Untitled (W-8tPPNV) (Autodesk Fusion 360 design; units mm, degrees)
Autodesk Fusion 360 part; units mm, degrees
sketch "Sketch1" plane through (0, 0, 0) normal (0, 1, 0) x (1, 0, 0)
  line L0 (5, -5) -> (-5, -5)
  line L1 (-5, -5) -> (-5, 5)
  line L2 (-5, 5) -> (5, 5)
  line L3 (5, 5) -> (5, -5)
  line L4 (2, -2) -> (-2, -2)
  line L5 (-2, -2) -> (-2, 2)
  line L6 (-2, 2) -> (2, 2)
  line L7 (2, 2) -> (2, -2)
  line L8 (0, 0) -> (-5, 5)
  line L9 (0, 0) -> (5, 5)
  line L10 (0, 0) -> (5, -5)
  line L11 (0, 0) -> (-5, -5)
  line L12 (-2.6745, 2.6745) -> (-3.0281, 2.321)
  line L13 (-2.6745, 2.6745) -> (-2.321, 3.0281)
  line L14 (2.8513, 2.8513) -> (3.2048, 2.4977)
  line L15 (2.8513, 2.8513) -> (2.4977, 3.2048)
  line L16 (3.0634, -3.0634) -> (2.7099, -3.417)
  line L17 (3.0634, -3.0634) -> (3.417, -2.7099)
  line L18 (-3.276, -3.276) -> (-3.6296, -2.9225)
  line L19 (-3.276, -3.276) -> (-2.9225, -3.6296)
  line L20 (-3.6296, -2.9225) -> (-1.3404, -0.6333)
  line L21 (-3.6296, -2.9225) -> (-5.7188, -5.0117)
  line L22 (-2.9225, -3.6296) -> (-0.6633, -1.3704)
  line L23 (-2.9225, -3.6296) -> (-5.0817, -5.7888)
  line L24 (-3.0281, 2.321) -> (-1.0788, 0.3717)
  line L25 (-3.0281, 2.321) -> (-5.7071, 5)
  line L26 (-2.321, 3.0281) -> (-5.3299, 6.037)
  line L27 (-2.321, 3.0281) -> (-0.2417, 0.9488)
  line L28 (2.4977, 3.2048) -> (0.4989, 1.206)
  line L29 (3.2048, 2.4977) -> (1.356, 0.6489)
  line L30 (2.4977, 3.2048) -> (5.6371, 6.3442)
  line L31 (3.2048, 2.4977) -> (6.2643, 5.5571)
  line L32 (3.417, -2.7099) -> (6.202, -5.4949)
  line L33 (2.7099, -3.417) -> (5.6299, -6.337)
  line L34 (2.7099, -3.417) -> (0.5835, -1.2907)
  line L35 (3.417, -2.7099) -> (1.3878, -0.6807)
  line L36 (-5, -5) -> (-4.2929, -4.2929)
  line L37 (-4.2929, -4.2929) -> (-3.0481, -5.5377)
  line L38 (-4.2929, -4.2929) -> (-5.4934, -3.0924)
  line L39 (-4.2929, -4.2929) -> (-3.8686, -3.8686)
  line L40 (-3.8686, -3.8686) -> (-5.7736, -1.9636)
  line L41 (-3.8686, -3.8686) -> (-1.4498, -6.2875)
  line L42 (5, -5) -> (4.2929, -4.2929)
  line L43 (-4.2929, -4.2929) -> (-4.0808, -4.505)
  line L44 (-4.2929, -4.2929) -> (-4.505, -4.0808)
  line L45 (-4.505, -4.0808) -> (-5.9877, -5.5634)
  line L46 (-4.0808, -4.505) -> (-5.3646, -5.7888)
  line L47 (4.2929, -4.2929) -> (2.8736, -5.7122)
  line L48 (4.2929, -4.2929) -> (5.8776, -2.7082)
  line L49 (4.2929, -4.2929) -> (4.505, -4.0808)
  line L50 (4.2929, -4.2929) -> (4.0808, -4.505)
  line L51 (4.0808, -4.505) -> (5.6075, -6.0318)
  line L52 (4.505, -4.0808) -> (6.2423, -5.8181)
  line L53 (4.2929, -4.2929) -> (3.8686, -3.8686)
  line L54 (3.8686, -3.8686) -> (5.8582, -1.879)
  line L55 (3.8686, -3.8686) -> (1.9311, -5.8061)
  line L56 (5, 5) -> (4.2929, 4.2929)
  line L57 (4.2929, 4.2929) -> (2.5, 6.0858)
  line L58 (4.2929, 4.2929) -> (6.5174, 2.0684)
  line L59 (4.2929, 4.2929) -> (3.8686, 3.8686)
  line L60 (3.8686, 3.8686) -> (1.9516, 5.7856)
  line L61 (3.8686, 3.8686) -> (5.6131, 2.1242)
  line L62 (4.2929, 4.2929) -> (4.0808, 4.505)
  line L63 (4.2929, 4.2929) -> (4.505, 4.0808)
  line L64 (4.0808, 4.505) -> (5.7085, 6.1328)
  line L65 (4.505, 4.0808) -> (6.2385, 5.8143)
  line L66 (-5, 5) -> (-4.2929, 4.2929)
  line L67 (-4.2929, 4.2929) -> (-5.6626, 2.9232)
  line L68 (-4.2929, 4.2929) -> (-2.644, 5.9418)
  line L69 (-4.2929, 4.2929) -> (-3.8686, 3.8686)
  line L70 (-3.8686, 3.8686) -> (-5.6859, 2.0514)
  line L71 (-3.8686, 3.8686) -> (-1.7234, 6.0139)
  line L72 (-4.2929, 4.2929) -> (-4.505, 4.0808)
  line L73 (-4.2929, 4.2929) -> (-4.0808, 4.505)
  line L74 (-4.0808, 4.505) -> (-7.0017, 7.426)
  line L75 (-4.505, 4.0808) -> (-6.1404, 5.7162)
  dimension "d5" = 0.5
  dimension "d6" = 0.5
  dimension "d7" = 0.5
  dimension "d8" = 0.5
  dimension "d9" = 0.5
  dimension "d10" = 0.5
  dimension "d11" = 0.5
  dimension "d12" = 0.5
  dimension "d13" = 1
  dimension "d14" = 0.6
  dimension "d15" = 1
  dimension "d16" = 0.3
  dimension "d17" = 0.3
  dimension "d18" = 0.3
  dimension "d19" = 0.3
  dimension "d20" = 0.6
  dimension "d21" = 1
  dimension "d22" = 0.6
  dimension "d23" = 0.3
  dimension "d24" = 0.3
  dimension "d25" = 1
  dimension "d26" = 0.6
  dimension "d27" = 0.3
  dimension "d28" = 0.3
  constraint perpendicular L0 L1
  constraint parallel L0 L2
  constraint parallel L1 L3
  constraint horizontal L0
  constraint coincident L8.start L9.start
  constraint perpendicular L4 L5
  constraint parallel L5 L7
  constraint horizontal L4
  constraint perpendicular L8 L9
  constraint perpendicular L9 L10
  constraint perpendicular L8 L11
  constraint coincident L8 L12.start
  constraint coincident L9 L14.start
  constraint coincident L10 L16.start
  constraint coincident L11 L18.start
  constraint perpendicular L18 L20
  constraint perpendicular L18 L21
  constraint perpendicular L19 L22
  constraint perpendicular L19 L23
  constraint perpendicular L12 L24
  constraint perpendicular L12 L25
  constraint perpendicular L13 L26
  constraint perpendicular L13 L27
  constraint perpendicular L15 L28
  constraint perpendicular L14 L29
  constraint perpendicular L15 L30
  constraint perpendicular L14 L31
  constraint perpendicular L17 L32
  constraint perpendicular L16 L33
  constraint perpendicular L16 L34
  constraint perpendicular L17 L35
  constraint perpendicular L23 L37
  constraint perpendicular L21 L38
  constraint perpendicular L21 L40
  constraint perpendicular L23 L41
  constraint perpendicular L38 L45
  constraint perpendicular L37 L46
  constraint perpendicular L33 L47
  constraint perpendicular L10 L48
  constraint perpendicular L47 L51
  constraint perpendicular L48 L52
  constraint perpendicular L32 L54
  constraint perpendicular L33 L55
  constraint perpendicular L30 L57
  constraint perpendicular L56 L58
  constraint perpendicular L30 L60
  constraint perpendicular L31 L61
  constraint perpendicular L57 L64
  constraint perpendicular L58 L65
  constraint perpendicular L8 L67
  constraint perpendicular L26 L68
  constraint perpendicular L8 L70
  constraint perpendicular L26 L71
  constraint perpendicular L68 L74
  constraint perpendicular L67 L75
  measures "d5" distance of L12.start L12.end
  measures "d6" distance of L12.start L13.end
  measures "d7" distance of L14.start L14.end
  measures "d8" distance of L14.start L15.end
  measures "d9" distance of L16.start L16.end
  measures "d10" distance of L16.start L17.end
  measures "d11" distance of L18.start L18.end
  measures "d12" distance of L18.start L19.end
  measures "d13" distance of L0.end L36.end
  measures "d14" distance of L36.end L39.end
  measures "d15" distance of L0.start L42.end
  measures "d16" distance of L36.end L43.end
  measures "d17" distance of L36.end L44.end
  measures "d18" distance of L42.end L49.end
  measures "d19" distance of L42.end L50.end
  measures "d20" distance of L42.end L53.end
  measures "d21" distance of L2.end L56.end
  measures "d22" distance of L56.end L59.end
  measures "d23" distance of L56.end L62.end
  measures "d24" distance of L56.end L63.end
  measures "d25" distance of L1.end L66.end
  measures "d26" distance of L66.end L69.end
  measures "d27" distance of L66.end L72.end
  measures "d28" distance of L66.end L73.end
extrude "Extrude1" add sketch "Sketch1" along normal blind 200 contours L3 L10 L42 L48 L49 L52 | L0 L10 L42 L47 L50 L51 | L10 L33 L47 L50 L53 L55 | L10 L32 L48 L49 L53 L54 | L10 L16 L33 L55 | L10 L17 L32 L54 | L0 L33 L47 L55 | L3 L32 L48 L54 | L4 L10 L16 L34 | L7 L10 L17 L35 | L7 L9 L10 | L4 L10 L11 | L0 L23 L37 L41 | L3 L31 L58 L61 | L5 L8 L11 | L6 L8 L9 | L11 L19 L23 L41 | L11 L23 L37 L39 L41 L43 | L9 L31 L58 L59 L61 L63 | L9 L14 L31 L61 | L4 L11 L19 L22 | L7 L9 L14 L29 | L6 L8 L13 L27 | L5 L8 L12 L24 | L6 L9 L15 L28 | L5 L11 L18 L20 | L11 L18 L21 L40 | L11 L21 L38 L39 L40 L44 | L9 L30 L57 L59 L60 L62 | L9 L15 L30 L60 | L8 L12 L25 L70 | L8 L13 L26 L71 | L0 L11 L36 L37 L43 L46 | L1 L11 L36 L38 L44 L45 | L1 L21 L38 L40 | L3 L9 L56 L58 L63 L65 | L2 L9 L56 L57 L62 L64 | L2 L30 L57 L60 | L8 L25 L67 L69 L70 L72 | L8 L26 L68 L69 L71 L73 | L1 L25 L67 L70 | L2 L26 L68 L71 | L1 L8 L66 L67 L72 L75 | L2 L8 L66 L68 L73 L74
sketch "Sketch2" plane through (0, 200, 0) normal (0, 1, 0) x (-1, 0, 0)
  line L0 (4.505, -4.0808) -> (5, -3.5858)
  line L1 (5, -3.5858) -> (5, -2.7373)
  line L2 (5, -2.7373) -> (4.2222, -3.5151)
  line L3 (4.2222, -3.5151) -> (2, -1.2929)
  line L4 (2, -1.2929) -> (2, 1.2929)
  line L5 (2, 1.2929) -> (4.2222, 3.5151)
  line L6 (4.2222, 3.5151) -> (5, 2.7373)
  line L7 (5, 2.7373) -> (5, 3.5858)
  line L8 (5, 3.5858) -> (4.505, 4.0808)
  line L9 (4.505, 4.0808) -> (5, 4.5757)
  line L10 (5, 4.5757) -> (5, 5)
  line L11 (5, 5) -> (4.5757, 5)
  line L12 (4.5757, 5) -> (4.0808, 4.505)
  line L13 (4.0808, 4.505) -> (3.5858, 5)
  line L14 (3.5858, 5) -> (2.7373, 5)
  line L15 (2.7373, 5) -> (3.5151, 4.2222)
  line L16 (3.5151, 4.2222) -> (1.2929, 2)
  line L17 (1.2929, 2) -> (-1.2929, 2)
  line L18 (-1.2929, 2) -> (-3.5151, 4.2222)
  line L19 (-3.5151, 4.2222) -> (-2.7373, 5)
  line L20 (-2.7373, 5) -> (-3.5858, 5)
  line L21 (-3.5858, 5) -> (-4.0808, 4.505)
  line L22 (-4.0808, 4.505) -> (-4.5757, 5)
  line L23 (-4.5757, 5) -> (-5, 5)
  line L24 (-5, 5) -> (-5, 4.5757)
  line L25 (-5, 4.5757) -> (-4.505, 4.0808)
  line L26 (-4.505, 4.0808) -> (-5, 3.5858)
  line L27 (-5, 3.5858) -> (-5, 2.7373)
  line L28 (-5, 2.7373) -> (-4.2222, 3.5151)
  line L29 (-4.2222, 3.5151) -> (-2, 1.2929)
  line L30 (-2, 1.2929) -> (-2, -1.2929)
  line L31 (-2, -1.2929) -> (-4.2222, -3.5151)
  line L32 (-4.2222, -3.5151) -> (-5, -2.7373)
  line L33 (-5, -2.7373) -> (-5, -3.5858)
  line L34 (-5, -3.5858) -> (-4.505, -4.0808)
  line L35 (-4.505, -4.0808) -> (-5, -4.5757)
  line L36 (-5, -4.5757) -> (-5, -5)
  line L37 (-5, -5) -> (-4.5757, -5)
  line L38 (-4.5757, -5) -> (-4.0808, -4.505)
  line L39 (-4.0808, -4.505) -> (-3.5858, -5)
  line L40 (-3.5858, -5) -> (-2.7373, -5)
  line L41 (-2.7373, -5) -> (-3.5151, -4.2222)
  line L42 (-3.5151, -4.2222) -> (-1.2929, -2)
  line L43 (-1.2929, -2) -> (1.2929, -2)
  line L44 (1.2929, -2) -> (3.5151, -4.2222)
  line L45 (3.5151, -4.2222) -> (2.7373, -5)
  line L46 (2.7373, -5) -> (3.5858, -5)
  line L47 (3.5858, -5) -> (4.0808, -4.505)
  line L48 (4.0808, -4.505) -> (4.5757, -5)
  line L49 (4.5757, -5) -> (5, -5)
  line L50 (5, -5) -> (5, -4.5757)
  line L51 (5, -4.5757) -> (4.505, -4.0808)
  line L52 (1.2929, 2) -> (-1.2929, 2)
  line L53 (-1.2929, 2) -> (-3.5151, 4.2222)
  line L54 (-3.5151, 4.2222) -> (-2.7373, 5)
  line L55 (-2.7373, 5) -> (-3.5858, 5)
  line L56 (-3.5858, 5) -> (-4.0808, 4.505)
  line L57 (-4.0808, 4.505) -> (-4.5757, 5)
  line L58 (-4.5757, 5) -> (-5, 5)
  line L59 (-5, 5) -> (-5, 4.5757)
  line L60 (-5, 4.5757) -> (-4.505, 4.0808)
  line L61 (-4.505, 4.0808) -> (-5, 3.5858)
  line L62 (-5, 3.5858) -> (-5, 2.7373)
  line L63 (-5, 2.7373) -> (-4.2222, 3.5151)
  line L64 (-4.2222, 3.5151) -> (-2, 1.2929)
  line L65 (-2, 1.2929) -> (-2, -1.2929)
  line L66 (-2, -1.2929) -> (-4.2222, -3.5151)
  line L67 (-4.2222, -3.5151) -> (-5, -2.7373)
  line L68 (-5, -2.7373) -> (-5, -3.5858)
  line L69 (-5, -3.5858) -> (-4.505, -4.0808)
  line L70 (-4.505, -4.0808) -> (-5, -4.5757)
  line L71 (-5, -4.5757) -> (-5, -5)
  line L72 (-5, -5) -> (-4.5757, -5)
  line L73 (-4.5757, -5) -> (-4.0808, -4.505)
  line L74 (-4.0808, -4.505) -> (-3.5858, -5)
  line L75 (-3.5858, -5) -> (-2.7373, -5)
  line L76 (-2.7373, -5) -> (-3.5151, -4.2222)
  line L77 (-3.5151, -4.2222) -> (-1.2929, -2)
  line L78 (-1.2929, -2) -> (1.2929, -2)
  line L79 (1.2929, -2) -> (3.5151, -4.2222)
  line L80 (3.5151, -4.2222) -> (2.7373, -5)
  line L81 (2.7373, -5) -> (3.5858, -5)
  line L82 (3.5858, -5) -> (4.0808, -4.505)
  line L83 (4.0808, -4.505) -> (4.5757, -5)
  line L84 (4.5757, -5) -> (5, -5)
  line L85 (5, -5) -> (5, -4.5757)
  line L86 (5, -4.5757) -> (4.505, -4.0808)
  line L87 (4.505, -4.0808) -> (5, -3.5858)
  line L88 (5, -3.5858) -> (5, -2.7373)
  line L89 (5, -2.7373) -> (4.2222, -3.5151)
  line L90 (4.2222, -3.5151) -> (2, -1.2929)
  line L91 (2, -1.2929) -> (2, 1.2929)
  line L92 (2, 1.2929) -> (4.2222, 3.5151)
  line L93 (4.2222, 3.5151) -> (5, 2.7373)
  line L94 (5, 2.7373) -> (5, 3.5858)
  line L95 (5, 3.5858) -> (4.505, 4.0808)
  line L96 (4.505, 4.0808) -> (5, 4.5757)
  line L97 (5, 4.5757) -> (5, 5)
  line L98 (5, 5) -> (4.5757, 5)
  line L99 (4.5757, 5) -> (4.0808, 4.505)
  line L100 (4.0808, 4.505) -> (3.5858, 5)
  line L101 (3.5858, 5) -> (2.7373, 5)
  line L102 (2.7373, 5) -> (3.5151, 4.2222)
  line L103 (3.5151, 4.2222) -> (1.2929, 2)
  constraint coincident L16.end L17.start
  constraint coincident L17.end L18.start
  constraint coincident L18.end L19.start
  constraint coincident L19.end L20.start
  constraint coincident L20.end L21.start
  constraint coincident L21.end L22.start
  constraint coincident L22.end L23.start
  constraint coincident L23.end L24.start
  constraint coincident L24.end L25.start
  constraint coincident L25.end L26.start
  constraint coincident L26.end L27.start
  constraint coincident L27.end L28.start
  constraint coincident L28.end L29.start
  constraint coincident L29.end L30.start
  constraint coincident L30.end L31.start
  constraint coincident L31.end L32.start
  constraint coincident L32.end L33.start
  constraint coincident L33.end L34.start
  constraint coincident L34.end L35.start
  constraint coincident L35.end L36.start
  constraint coincident L36.end L37.start
  constraint coincident L37.end L38.start
  constraint coincident L38.end L39.start
  constraint coincident L39.end L40.start
  constraint coincident L40.end L41.start
  constraint coincident L41.end L42.start
  constraint coincident L42.end L43.start
  constraint coincident L43.end L44.start
  constraint coincident L44.end L45.start
  constraint coincident L45.end L46.start
  constraint coincident L46.end L47.start
  constraint coincident L47.end L48.start
  constraint coincident L48.end L49.start
  constraint coincident L49.end L50.start
  constraint coincident L50.end L51.start
  constraint coincident L0.start L51.end
  constraint coincident L0.end L1.start
  constraint coincident L1.end L2.start
  constraint coincident L2.end L3.start
  constraint coincident L3.end L4.start
  constraint coincident L4.end L5.start
  constraint coincident L5.end L6.start
  constraint coincident L6.end L7.start
  constraint coincident L7.end L8.start
  constraint coincident L8.end L9.start
  constraint coincident L9.end L10.start
  constraint coincident L10.end L11.start
  constraint coincident L11.end L12.start
  constraint coincident L12.end L13.start
  constraint coincident L13.end L14.start
  constraint coincident L14.end L15.start
  constraint coincident L15.end L16.start
